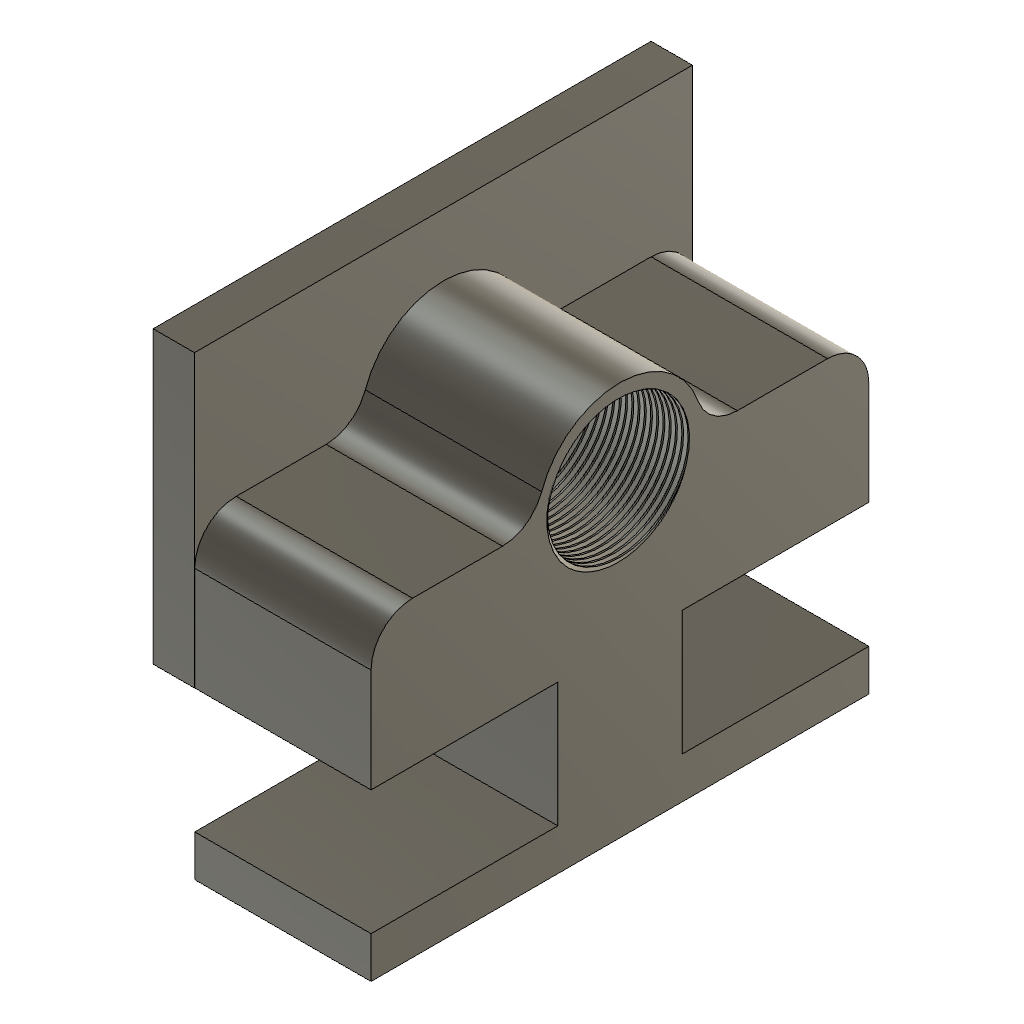
ASSEMBLE+1 (Autodesk Fusion 360 archive; units mm, degrees)
design "body 3"
part number: 2026-10-03-21-04-10-954
part number: 2026-10-07-15-16-42-855
Autodesk Fusion 360 part; units mm, degrees
sketch "Sketch1" plane through (0, 0, 0) normal (1, 0, 0) x (0, 1, 0)
  circle A0 centre (0.0527, 74.7178) radius 20
  line L0 (15.0529, 9.7178) -> (60.0529, 9.718)
  line L1 (60.0529, 9.718) -> (60.0529, -0.282)
  circle A1 centre (0.0527, 74.7178) radius 15
  line L2 (15.0529, 9.7178) -> (15.0528, 39.7178)
  line L3 (0.0722, -19.5213) -> (0.0718, 100.4787)
  line L4 (15.0528, 39.7178) -> (60.0528, 39.718)
  line L5 (60.0528, 39.718) -> (60.0527, 64.718)
  line L6 (50.0527, 74.7179) -> (0.0527, 74.7178)
  line L7 (60.0529, -0.282) -> (0.0529, -0.2822)
  line L8 (-14.9088, 39.7177) -> (-59.9088, 39.7176)
  line L9 (-59.9087, -0.2824) -> (0.0913, -0.2822)
  line L10 (-14.9087, 9.7177) -> (-59.9087, 9.7176)
  line L11 (-14.9087, 9.7177) -> (-14.9088, 39.7177)
  line L12 (-59.9088, 39.7176) -> (-59.9089, 64.7176)
  line L13 (-59.9087, 9.7176) -> (-59.9087, -0.2824)
  line L14 (-49.9089, 74.7176) -> (0.0911, 74.7178)
  arc A2 (60.0527, 64.718) -> (50.0527, 74.7179) centre (50.0527, 64.7179) ccw
  arc A3 (-49.9089, 74.7176) -> (-59.9089, 64.7176) centre (-49.9089, 64.7176) ccw
  point P0 (0.0722, -19.5213)
  point P1 (60.0527, 74.718)
  dimension "d3" = 40
  dimension "d41" = 10
  dimension "d44" = -5
  dimension "d77" = 45
  dimension "d81" = 30
  dimension "d83" = 120
  dimension "d84" = 45
  dimension "d85" = 35
  dimension "d86" = 60
  dimension "d87" = 60
  dimension "d88" = 10
  constraint perpendicular L0 L1
  constraint perpendicular L0 L2
  constraint coincident P0 L3.start
  constraint perpendicular L2 L4
  constraint perpendicular L4 L5
  constraint perpendicular L3 L6
  constraint perpendicular L3 L7
  constraint symmetric L0.start L3 L10.start
  constraint symmetric L0.end L3 L10.end
  constraint symmetric L1.end L3 L9.start
  constraint symmetric L2.end L3 L8.start
  constraint symmetric L3 L4.end L8.end
  constraint symmetric L3 A0.centre L14.end
  constraint symmetric L3 L7.end L9.end
  constraint coincident A0.centre A1.centre
  constraint coincident P1 L5
  constraint coincident P1 L6
  constraint tangent L5 A2
  constraint tangent L6 A2
  constraint tangent L12 A3
  constraint tangent L14 A3
  constraint equal A2 A3
  measures "d3" diameter of A0
  measures "d41" distance of L0.end L1.end
  measures "d77" horizontal distance of L0.start L0.end
  measures "d81" distance of L0.start L2.end
  measures "d83" distance of P0 L3.end
  measures "d84" distance of L2.end L4.end
  measures "d85" distance of L4.end P1
  measures "d86" distance of P1 A0.centre
  measures "d87" distance of L1.end L7.end
  measures "d88" radius of A2
extrude "Extrude6" add sketch "Sketch1" along normal blind 42.5 contours A0 A1 L3 L6 | A0 L0 L1 L2 L3 L4 L5 L6 L7 L9 A2 | A0 A1 L3 L6 | A0 A1 L3 L14 | A0 L3 L7 L8 L9 L10 L11 L12 L13 L14 A3 | A0 A1 L3 L14 makes body 1
fillet "Fillet9" radius 10 1 edges at (21.25, -19.9473, 74.7177) on bodies 1
fillet "Fillet10" radius 10 1 edges at (21.25, 20.0527, 74.7178) on bodies 1
thread "Thread1" "ISO Metric profile 35.0 M35x1.5 M35x1.5 6H" major diameter 35.208 minor diameter 33.526 pitch 1.5 angle 60 modelled right hand crest width 0.4036 on face at (14.1667, 14.9781, 73.2243) crest through (0.375, 16.8157, 74.7178) on bodies 1
sketch "Sketch3" plane through (0, 0, 0) normal (-1, 0, 0) x (0, -1, 0)
  spline S0 degree 3 poles (4.5145, 91.719) (6.7034, 91.0755) (8.7462, 90.0126) (12.2908, 87.1733) (13.7634, 85.4306) (15.9445, 81.4948) (16.6387, 79.3436) (17.1573, 74.9162) (16.9846, 72.6836) (16.0241, 69.2506) (15.508, 68.0015) (14.1935, 65.6598) (13.4014, 64.5745) (12.4887, 63.5951) knots 0 0 0 0 0.684446 0.684446 1.362736 1.362736 2.03487 2.03487 2.700845 2.700845 3.105174 3.105174 3.507164 3.507164 3.507164 3.507164
  arc A0 (-12.594, 63.5951) -> (12.4887, 63.5951) centre (-0.0527, 74.7178) ccw
  spline S1 degree 3 poles (-12.594, 63.5951) (-14.0887, 65.199) (-15.2543, 67.0806) (-16.8096, 71.2032) (-17.1771, 73.4073) (-17.0496, 77.8537) (-16.5481, 80.0529) (-14.7251, 84.1563) (-13.4141, 86.0178) (-10.7797, 88.5382) (-9.6638, 89.3754) (-7.2506, 90.772) (-5.9611, 91.3247) (-4.6198, 91.719) knots 0 0 0 0 0.65773 0.65773 1.321613 1.321613 1.991648 1.991648 2.667834 2.667834 3.084534 3.084534 3.503568 3.503568 3.503568 3.503568
  arc A1 (4.5145, 91.719) -> (-4.6198, 91.719) centre (-0.0527, 74.7178) ccw
  line L0 (-15.0528, 39.7178) -> (-15.0529, 9.7178)
  line L1 (-15.0529, 9.7178) -> (-60.0529, 9.718)
  line L2 (-60.0529, 9.718) -> (-60.0529, -0.282)
  line L3 (-60.0529, -0.282) -> (59.9087, -0.2824)
  line L4 (59.9087, -0.2824) -> (59.9087, 9.7176)
  line L5 (59.9087, 9.7176) -> (14.9087, 9.7177)
  line L6 (14.9087, 9.7177) -> (14.9088, 39.7177)
  line L7 (14.9088, 39.7177) -> (59.9088, 39.7176)
  line L8 (59.9088, 39.7176) -> (59.9089, 64.7176)
  arc A2 (59.9089, 64.7176) -> (49.9089, 74.7176) centre (49.9089, 64.7176) ccw
  line L9 (49.9089, 74.7176) -> (28.2316, 74.7177)
  arc A3 (18.8035, 81.3844) -> (28.2316, 74.7177) centre (28.2317, 84.7177) ccw
  arc A4 (18.8035, 81.3844) -> (-18.9088, 81.3845) centre (-0.0527, 74.7178) ccw
  arc A5 (-28.3369, 74.7179) -> (-18.9088, 81.3845) centre (-28.3369, 84.7179) ccw
  line L10 (-28.3369, 74.7179) -> (-50.0527, 74.7179)
  arc A6 (-50.0527, 74.7179) -> (-60.0527, 64.718) centre (-50.0527, 64.7179) ccw
  line L11 (-60.0527, 64.718) -> (-60.0528, 39.718)
  line L12 (-60.0528, 39.718) -> (-15.0528, 39.7178)
  line L13 (-60.0527, 109.7178) -> (59.9473, 109.7178)
  line L14 (59.9473, 109.7178) -> (59.9473, 39.7178)
  line L15 (59.9473, 39.7178) -> (-60.0527, 39.7178)
  line L16 (-60.0527, 39.7178) -> (-60.0527, 109.7178)
  line L17 (-60.0527, 109.7178) -> (59.9473, 39.7178) construction
  line L18 (59.9473, 109.7178) -> (-60.0527, 39.7178) construction
  point P0 (-0.0527, 74.7178)
  dimension "d97" = 120
  dimension "d98" = 70
  constraint horizontal L13
  constraint perpendicular L13 L14
  constraint parallel L13 L15
  constraint parallel L14 L16
  constraint coincident L17 P0
  constraint coincident L18 P0
  constraint coincident P0 A0.centre
  measures "d97" distance of L14.end L15.end
  measures "d98" distance of L13.end L14.end
extrude "Extrude7" add sketch "Sketch3" along normal blind 10 contours S0 A0 S1 A1 | L7 L8 A2 L9 A3 A4 A5 L10 A6 L11 L12 L15 L16 | L8 A2 L9 A3 A4 A5 L10 A6 L13 L14 L15 L16 bodies 1
copy_body "Body->Comp5" bodies 1 removing the originals makes body 2 in component "Slider"
component "Slider" placed x (1, 0, 0) y (0, 1, 0) z (0, 0, 1) at (0, 0, 0)
named bodies: "Slider"

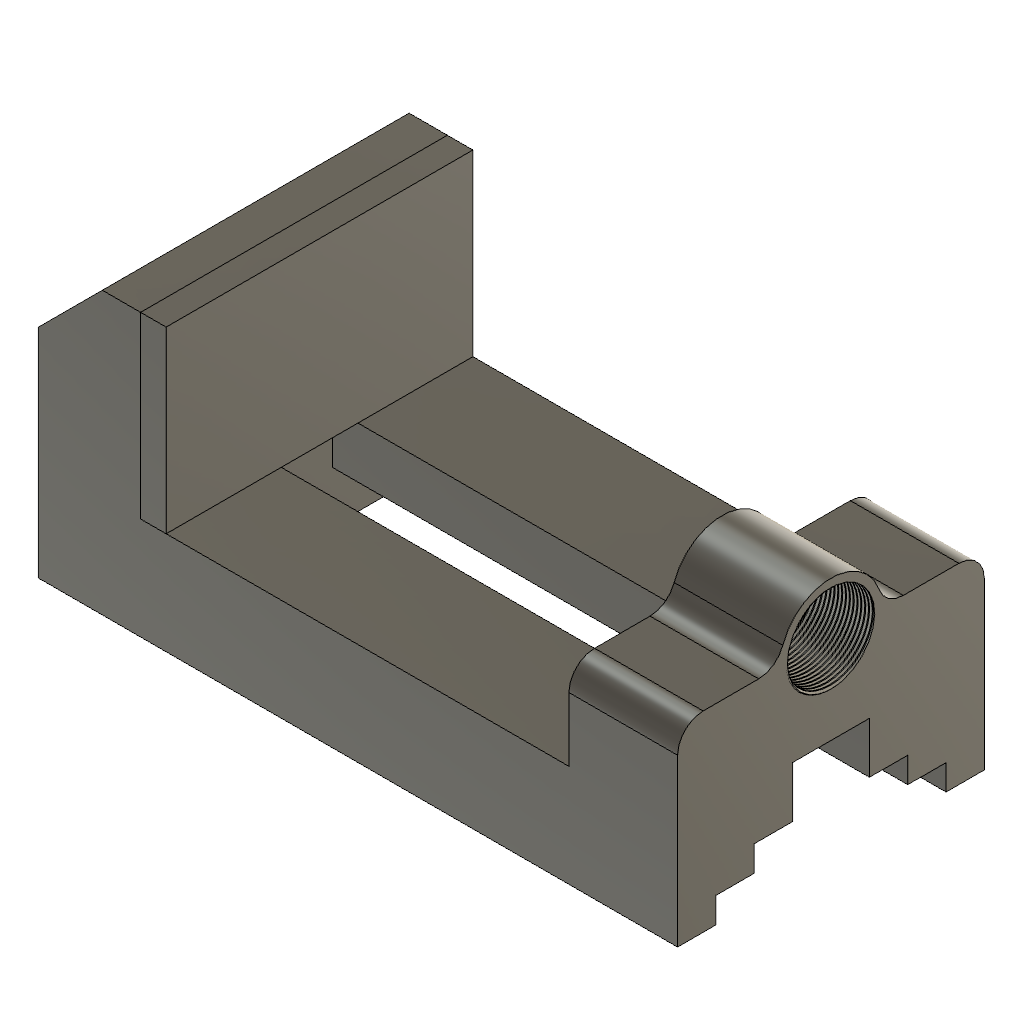
design "body 1"
part number: 2026-10-02-19-15-55-777
part number: 2026-10-07-14-51-14-038
part number: 2026-10-07-14-51-19-169
Autodesk Fusion 360 part; units mm, degrees
sketch "Sketch1" plane through (0, 0, 0) normal (0, 0, 1) x (1, 0, 0)
  line L0 (125, 60) -> (-125, 60)
  line L1 (-125, 60) -> (-125, -60)
  line L2 (-125, -60) -> (125, -60)
  line L3 (125, -60) -> (125, 60)
  line L4 (125, 60) -> (-125, -60) construction
  line L5 (-125, 60) -> (125, -60) construction
  line L6 (-50, 60) -> (60, 60)
  dimension "d1" = 250
  dimension "d2" = 120
  constraint horizontal L0
  constraint perpendicular L0 L1
  constraint parallel L0 L2
  constraint parallel L1 L3
  constraint coincident L4 origin
  constraint coincident L5 origin
  constraint horizontal L6
  constraint coincident L0 L6.start
  measures "d1" distance of L1.end L2.end
  measures "d2" distance of L0.end L1.end
extrude "Extrude3" add sketch "Sketch1" along normal blind 110 makes body 1
sketch "Sketch4" plane through (0, 0, 110) normal (0, 0, 1) x (-1, 0, 0)
  line L0 (125, -60) -> (125, 60)
  line L1 (125, 60) -> (-125, 60)
  line L2 (-125, 60) -> (-125, -60)
  line L3 (-125, -60) -> (125, -60)
  line L4 (85, -60) -> (85, 60)
  line L5 (-82.5, -60) -> (-82.5, 60)
  dimension "d19" = 40
  dimension "d20" = 167.5
  constraint coincident L3 L4.start
  constraint coincident L1 L4.end
  constraint perpendicular L1 L4
  constraint coincident L3 L5.start
  constraint coincident L1 L5.end
  constraint perpendicular L1 L5
  measures "d19" distance of L0 L4
  measures "d20" distance of L4 L5
extrude "Extrude4" cut sketch "Sketch4" against normal blind 70 contours L1 L3 L4 L5 bodies 1
sketch "Sketch6" plane through (125, 0, 0) normal (1, 0, 0) x (0, 1, 0)
  line L0 (-60, 0) -> (60, 0)
  line L1 (60, 0) -> (60, 110)
  line L2 (60, 110) -> (-60, 110)
  line L3 (-60, 110) -> (-60, 0)
  line L4 (-60, 75) -> (60, 75)
  circle A0 centre (0, 75) radius 20
  circle A1 centre (0, 75) radius 15
  line L5 (-45, 0) -> (-45, 10)
  line L6 (-30, 10) -> (-30, 20)
  line L7 (-15, 20) -> (-15, 40)
  line L8 (-45, 10) -> (-30, 10)
  line L9 (-30, 20) -> (-15, 20)
  line L10 (-15, 40) -> (0.0005, 40)
  line L11 (45, 0) -> (45, 10)
  line L12 (45, 10) -> (30, 10)
  line L13 (30, 20) -> (15, 20)
  line L14 (30, 10) -> (30, 20)
  line L15 (15, 20) -> (15, 40)
  line L16 (0.0005, 40) -> (15, 40)
  point P0 (60, 0)
  dimension "d26" = 75
  dimension "d27" = 40
  dimension "d29" = -5
  dimension "d30" = 10
  dimension "d32" = 10
  dimension "d34" = 20
  dimension "d56" = 40
  dimension "d57" = 45
  dimension "d58" = 30
  dimension "d59" = 15
  constraint coincident L3 L4.start
  constraint coincident L1 L4.end
  constraint perpendicular L1 L4
  constraint midpoint L4 A0.centre
  constraint coincident L0 L5.start
  constraint perpendicular L0 L5
  constraint vertical L6
  constraint vertical L7
  constraint perpendicular L6 L8
  measures "d26" distance of L0 L4
  measures "d27" diameter of A0
  measures "d30" distance of L5.start L5.end
  measures "d32" distance of L6.start L6.end
  measures "d34" distance of L7.start L7.end
  measures "d56" distance of L0 L10
  measures "d57" distance of L3 L7
  measures "d58" distance of L3 L6
  measures "d59" distance of L3 L5
extrude "Extrude5" cut sketch "Sketch6" against normal blind 90 contours L1 L2 L3 L4 A0 bodies 1
extrude "Extrude6" cut sketch "Sketch6" against normal blind 210 contours L0 L5 L6 L7 L8 L9 L10 L11 L12 L13 L14 L15 L16 | L4 A1 | L4 A1 bodies 1
fillet "Fillet1" radius 10 1 edges at (103.75, -60, 75) on bodies 1
fillet "Fillet2" radius 10 1 edges at (103.75, -20, 75) on bodies 1
fillet "Fillet3" radius 10 1 edges at (103.75, 20, 75) on bodies 1
fillet "Fillet4" radius 10 1 edges at (103.75, 60, 75) on bodies 1
sketch "Sketch7" plane through (0, 0, 40) normal (0, 0, 1) x (-1, 0, 0)
  line L0 (85, -60) -> (85, -15)
  line L1 (85, 60) -> (-82.5, 60)
  line L2 (-82.5, -15) -> (-82.5, -60)
  line L3 (-82.5, -60) -> (85, -60)
  line L4 (-40, -59) -> (-40, 59)
  line L5 (-40, 59) -> (-82.5, 59)
  line L6 (-40, -59) -> (-82.5, -59)
  line L7 (-82.5, 15) -> (85, 15)
  line L8 (85, 15) -> (85, 60)
  line L9 (85, -15) -> (-82.5, -15)
  line L10 (-82.5, 60) -> (-82.5, 15)
  dimension "d50" = 118
  dimension "d51" = 42.5
  dimension "d52" = 1
  constraint vertical L4
  constraint coincident L2 L5.end
  constraint perpendicular L2 L5
  constraint coincident L2 L6.end
  constraint perpendicular L2 L6
  measures "d50" distance of L4.start L4.end
  measures "d51" distance of L2 L4
  measures "d52" distance of L3 L4.start
chamfer "Chamfer2" distance 25 angle 45 1 edges at (-125, 0, 110) tangent chain off on bodies 1
thread "Thread1" "ISO Metric profile 35.0 M35x1.5 M35x1.5 6H" major diameter 35.208 minor diameter 33.526 pitch 1.5 angle 60 modelled right hand crest width 0.4036 on face at (110.8333, 14.9255, 76.4935) crest through (124.625, 16.763, 75) on bodies 1
sketch "Sketch8" plane through (-85, 0, 0) normal (1, 0, 0) x (0, 1, 0)
  line L0 (60, 110) -> (-60, 110)
  line L1 (-60, 110) -> (-60, 40)
  line L2 (-60, 40) -> (-15, 40)
  line L3 (-15, 40) -> (-15, 20)
  line L4 (-15, 20) -> (-30, 20)
  line L5 (-30, 20) -> (-30, 10)
  line L6 (-30, 10) -> (-45, 10)
  line L7 (-45, 10) -> (-45, 0)
  line L8 (-45, 0) -> (45, 0)
  line L9 (45, 0) -> (45, 10)
  line L10 (45, 10) -> (30, 10)
  line L11 (30, 10) -> (30, 20)
  line L12 (30, 20) -> (15, 20)
  line L13 (15, 20) -> (15, 40)
  line L14 (15, 40) -> (60, 40)
  line L15 (60, 40) -> (60, 110)
  line L16 (-60, 110) -> (60, 110)
  line L17 (60, 110) -> (60, 40)
  line L18 (60, 40) -> (-60, 40)
  line L19 (-60, 40) -> (-60, 110)
  constraint horizontal L16
  constraint vertical L17
  constraint horizontal L18
  constraint vertical L19
  constraint coincident L14.end L15.start
  constraint coincident L0.end L1.start
extrude "Extrude8" add sketch "Sketch8" along normal blind 10 separate body contours L0 L1 L2 L14 L15 L16 L17 L18 L19 makes body 2
copy_body "Body->Comp1" bodies 2 removing the originals makes body 3 in component "rect"
copy_body "Body->Comp2" bodies 1 removing the originals makes body 4 in component "base"
component "rect" placed x (1, 0, 0) y (0, 1, 0) z (0, 0, 1) at (0, 0, 0)
component "base" placed x (1, 0, 0) y (0, 1, 0) z (0, 0, 1) at (0, 0, 0)
equation "d20 = 125 mm + 42.5 mm"
named bodies: "base", "rect"
